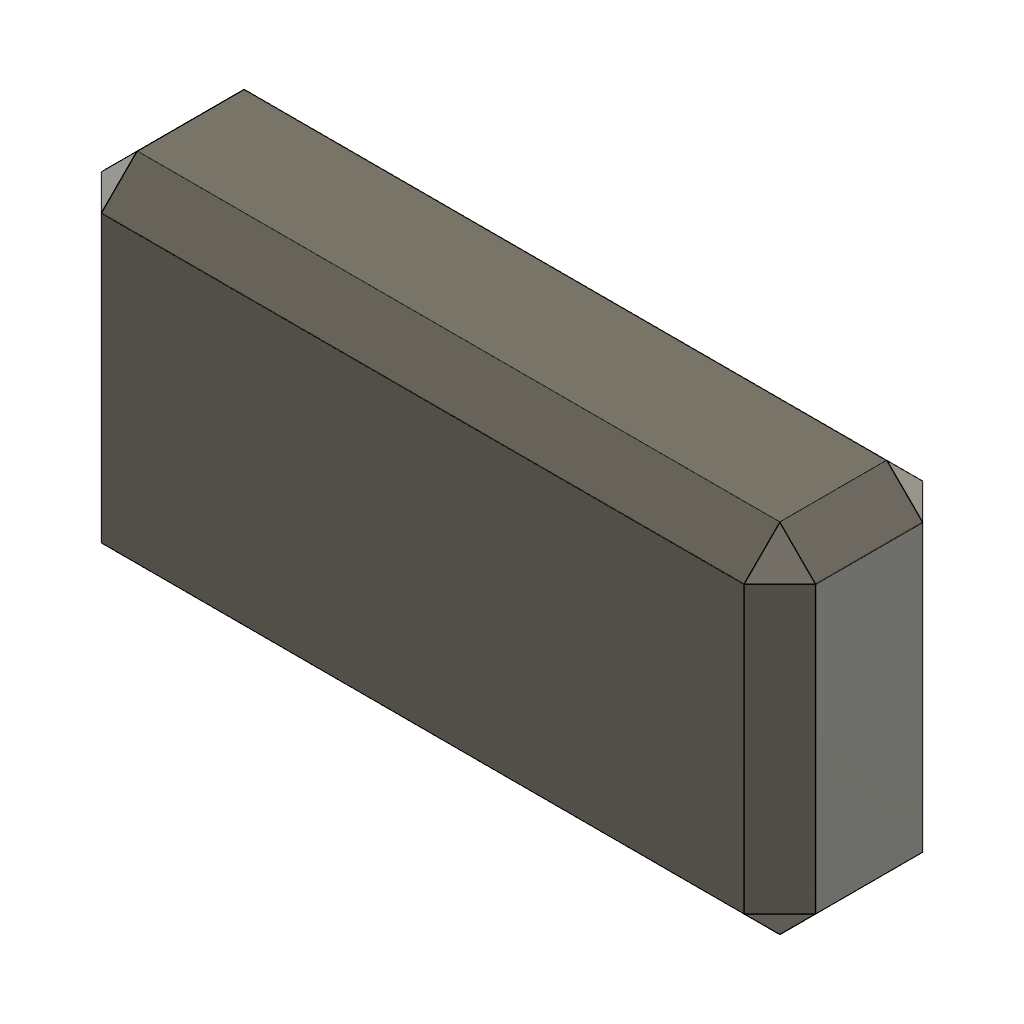
chamfer_box_all_edges (Autodesk Fusion 360 design; units mm, degrees)
part number: 2026-11-12-22-56-56-430
Autodesk Fusion 360 part; units mm, degrees
sketch "Sketch1" plane through (0, 0, 0) normal (0, 0, 1) x (1, 0, 0)
  line L0 (0, 0) -> (20, 0)
  line L1 (20, 0) -> (20, 10)
  line L2 (20, 10) -> (0, 10)
  line L3 (0, 10) -> (0, 0)
extrude "Extrude1" add sketch "Sketch1" along normal blind 5
chamfer "Chamfer1" distance 1 angle 45 12 edges at (10, 10, 0) (0, 10, 2.5) (10, 10, 5) (20, 10, 2.5) (20, 5, 0) (20, 5, 5) (20, 0, 2.5) (10, 0, 0) (10, 0, 5) (0, 0, 2.5) (0, 5, 0) (0, 5, 5) tangent chain off
